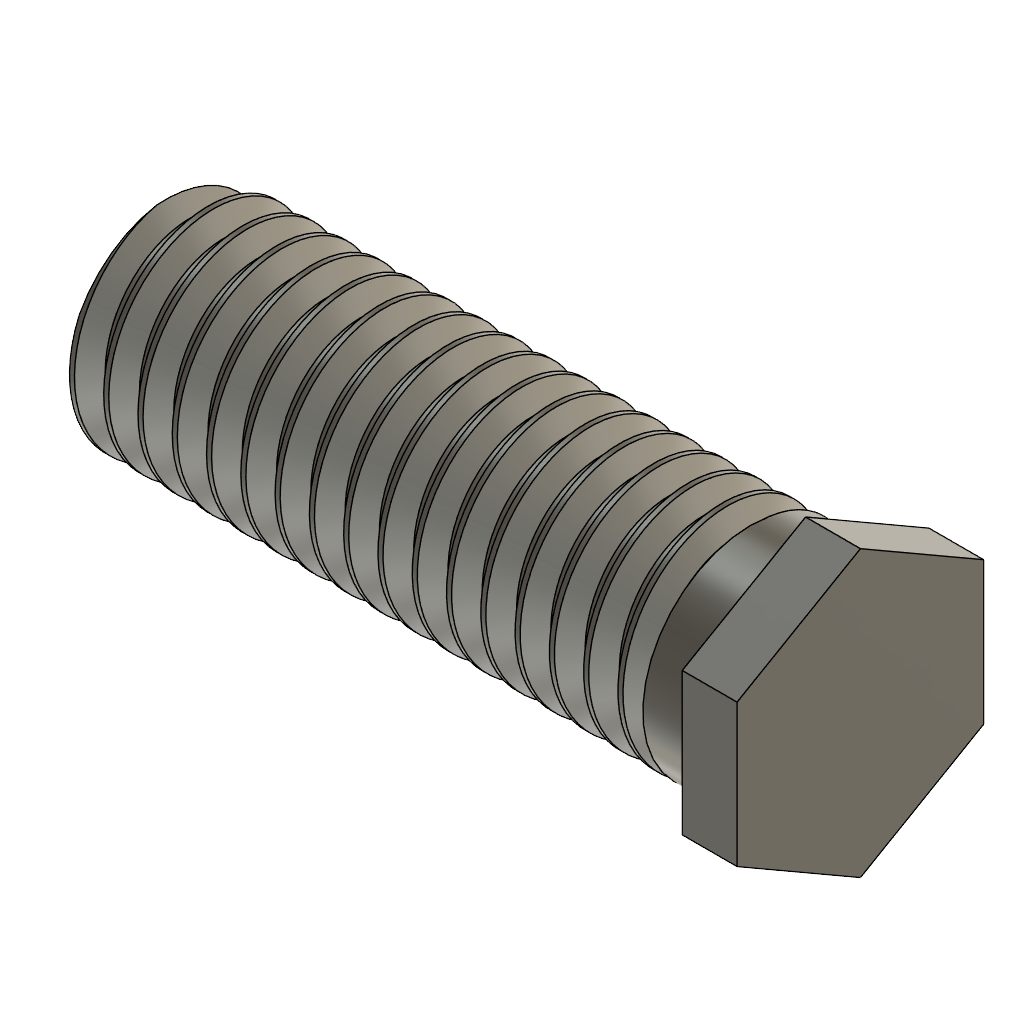
showerhead (Assembly) (Autodesk Fusion 360 archive; units mm, degrees)
design "screw_1_nozzle"
part number: 2026-10-19-10-13-48-495
Autodesk Fusion 360 part; units mm, degrees
sketch "Sketch1" plane through (0, 0, 0) normal (1, 0, 0) x (0, 1, 0)
  circle A0 centre (0, 0) radius 4
  line L0 (-4.4985, 2.5972) -> (-4.4985, -2.5972)
  line L1 (-4.4985, -2.5972) -> (0, -5.1944)
  line L2 (0, -5.1944) -> (4.4985, -2.5972)
  line L3 (4.4985, -2.5972) -> (4.4985, 2.5972)
  line L4 (4.4985, 2.5972) -> (0, 5.1944)
  line L5 (0, 5.1944) -> (-4.4985, 2.5972)
  constraint coincident A0.centre origin
extrude "Extrude1" add sketch "Sketch1" against normal blind 25 contours A0
extrude "Extrude2" add sketch "Sketch1" against normal blind 2
thread "Thread1" "ISO Metric profile 8.0 M8x1.25 M8x1.25 6g" major diameter 7.866 minor diameter 6.4455 pitch 1.25 angle 60 modelled right hand crest width 0.1833 on face at (-9.6667, 3.9801, -0.3983) from (-4, 0, 0) to (-25, 0, 0) crest through (-1.6875, 3.933, 0)

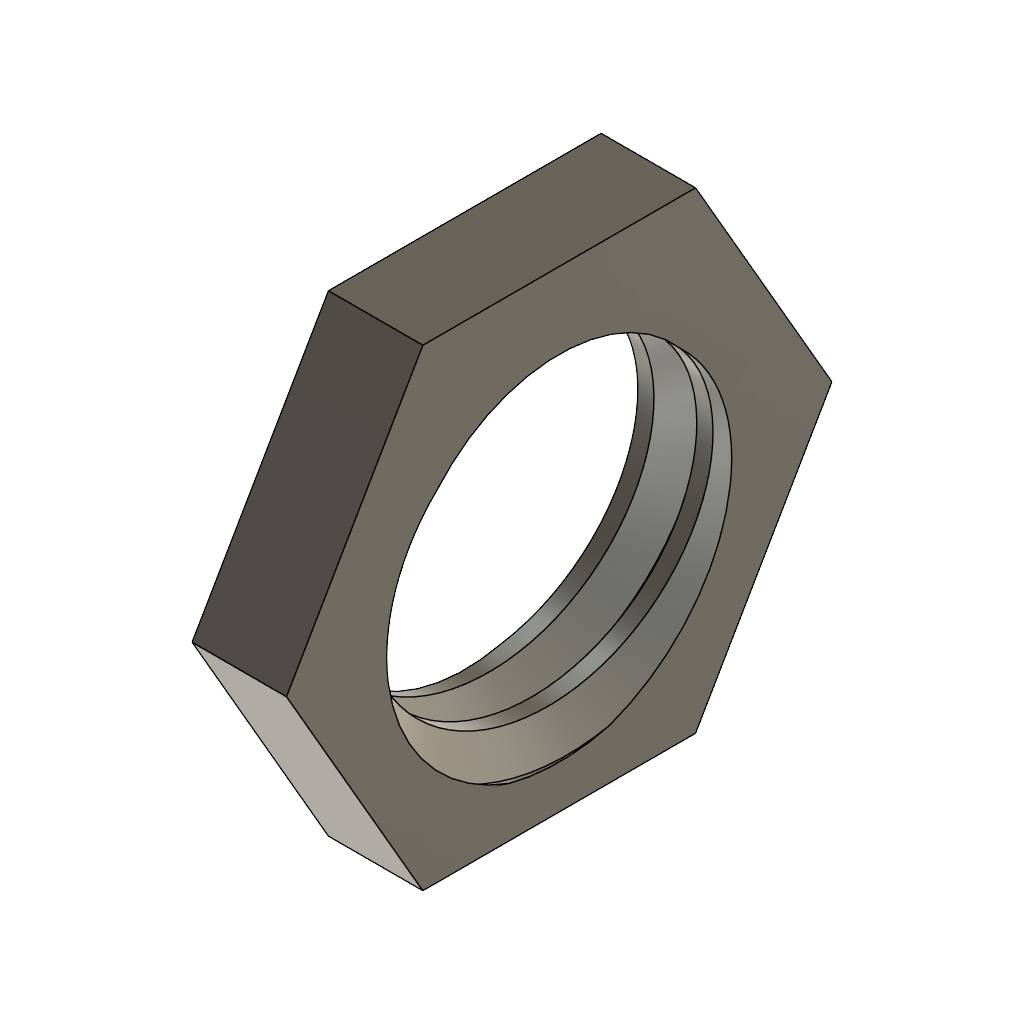
design "nut_1_nozzle"
part number: 2026-10-19-10-17-36-750
Autodesk Fusion 360 part; units mm, degrees
sketch "Sketch1" plane through (0, 0, 0) normal (1, 0, 0) x (0, 1, 0)
  circle A0 centre (0, 0) radius 4
  line L0 (-2.8868, 5) -> (-5.7735, 0)
  line L1 (-5.7735, 0) -> (-2.8868, -5)
  line L2 (-2.8868, -5) -> (2.8868, -5)
  line L3 (2.8868, -5) -> (5.7735, 0)
  line L4 (5.7735, 0) -> (2.8868, 5)
  line L5 (2.8868, 5) -> (-2.8868, 5)
  constraint coincident A0.centre origin
extrude "Extrude1" add sketch "Sketch1" against normal blind 2
thread "Thread1" "ISO Metric profile 8.0 M8x1.25 M8x1.25 6H" major diameter 8.17 minor diameter 6.7795 pitch 1.25 angle 60 modelled right hand crest width 0.343 on face at (-1.3333, 3.995, -0.1994) crest through (-0.3125, 3.3898, 0)

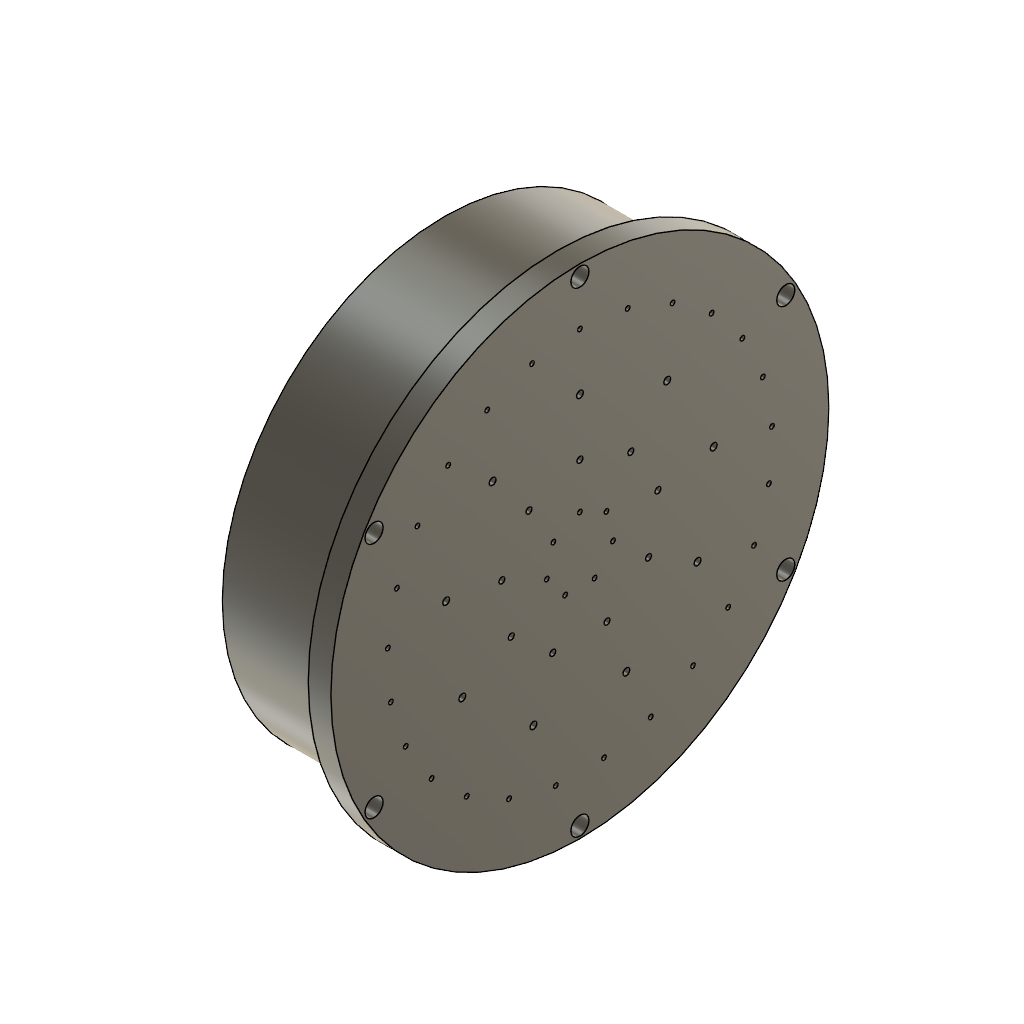
design "showerhead"
part number: 2026-10-19-09-36-01-385
Autodesk Fusion 360 part; units mm, degrees
sketch "Sketch1" plane through (0, 0, 0) normal (1, 0, 0) x (0, 1, 0)
  circle A0 centre (0, 0) radius 110
  circle A1 centre (0, 0) radius 90
  dimension "d1" = 220
  constraint coincident A0.centre A1.centre
  constraint concentric A0 A1
  measures "d1" diameter of A0
extrude "Extrude2" add sketch "Sketch1" along normal blind 10 contours A1
sketch "Sketch3" plane through (10, 0, 0) normal (1, 0, 0) x (0, 1, 0)
  circle A0 centre (0, 0) radius 90
  circle A1 centre (0, 85) radius 1
extrude "Extrude4" cut sketch "Sketch3" against normal blind 31 contours A1
pattern_circular "C-Pattern1" count 25 over 360 about axis through (1.75, 0, 0) along (1, 0, 0) of "Extrude4"
sketch "Sketch4" plane through (10, 0, 0) normal (1, 0, 0) x (0, 1, 0)
  circle A0 centre (0, 0) radius 90
  circle A1 centre (0, 85) radius 1
  circle A2 centre (-21.1386, 82.3296) radius 1
  circle A3 centre (-40.9491, 74.4861) radius 1
  circle A4 centre (-58.1865, 61.9623) radius 1
  circle A5 centre (-71.7679, 45.5453) radius 1
  circle A6 centre (-80.8398, 26.2664) radius 1
  circle A7 centre (-84.8323, 5.3372) radius 1
  circle A8 centre (-83.4944, -15.9274) radius 1
  circle A9 centre (-76.9103, -36.1912) radius 1
  circle A10 centre (-65.4936, -54.181) radius 1
  circle A11 centre (-49.9617, -68.7664) radius 1
  circle A12 centre (-31.2906, -79.031) radius 1
  circle A13 centre (-10.6533, -84.3298) radius 1
  circle A14 centre (10.6533, -84.3298) radius 1
  circle A15 centre (31.2906, -79.031) radius 1
  circle A16 centre (49.9617, -68.7664) radius 1
  circle A17 centre (65.4936, -54.181) radius 1
  circle A18 centre (76.9103, -36.1912) radius 1
  circle A19 centre (83.4944, -15.9274) radius 1
  circle A20 centre (84.8323, 5.3372) radius 1
  circle A21 centre (80.8398, 26.2664) radius 1
  circle A22 centre (71.7679, 45.5453) radius 1
  circle A23 centre (58.1865, 61.9623) radius 1
  circle A24 centre (40.9491, 74.4861) radius 1
  circle A25 centre (21.1386, 82.3296) radius 1
  circle A26 centre (0, 60) radius 1.5
extrude "Extrude5" cut sketch "Sketch4" against normal blind 20 contours A26
pattern_circular "C-Pattern2" count 9 over 360 about axis through (1.75, 0, 0) along (1, 0, 0) of "Extrude5"
sketch "Sketch5" plane through (10, 0, 0) normal (1, 0, 0) x (0, 1, 0)
  circle A0 centre (0, 60) radius 1.5
  circle A1 centre (0, 0) radius 90
  circle A2 centre (0, 85) radius 1
  circle A3 centre (-21.1386, 82.3296) radius 1
  circle A4 centre (-40.9491, 74.4861) radius 1
  circle A5 centre (-58.1865, 61.9623) radius 1
  circle A6 centre (-71.7679, 45.5453) radius 1
  circle A7 centre (-80.8398, 26.2664) radius 1
  circle A8 centre (-84.8323, 5.3372) radius 1
  circle A9 centre (-83.4944, -15.9274) radius 1
  circle A10 centre (-76.9103, -36.1912) radius 1
  circle A11 centre (-65.4936, -54.181) radius 1
  circle A12 centre (-49.9617, -68.7664) radius 1
  circle A13 centre (-31.2906, -79.031) radius 1
  circle A14 centre (-10.6533, -84.3298) radius 1
  circle A15 centre (10.6533, -84.3298) radius 1
  circle A16 centre (31.2906, -79.031) radius 1
  circle A17 centre (49.9617, -68.7664) radius 1
  circle A18 centre (65.4936, -54.181) radius 1
  circle A19 centre (76.9103, -36.1912) radius 1
  circle A20 centre (83.4944, -15.9274) radius 1
  circle A21 centre (84.8323, 5.3372) radius 1
  circle A22 centre (80.8398, 26.2664) radius 1
  circle A23 centre (71.7679, 45.5453) radius 1
  circle A24 centre (58.1865, 61.9623) radius 1
  circle A25 centre (40.9491, 74.4861) radius 1
  circle A26 centre (21.1386, 82.3296) radius 1
  circle A27 centre (-38.5673, 45.9627) radius 1.5
  circle A28 centre (-59.0885, 10.4189) radius 1.5
  circle A29 centre (-51.9615, -30) radius 1.5
  circle A30 centre (-20.5212, -56.3816) radius 1.5
  circle A31 centre (20.5212, -56.3816) radius 1.5
  circle A32 centre (51.9615, -30) radius 1.5
  circle A33 centre (59.0885, 10.4189) radius 1.5
  circle A34 centre (38.5673, 45.9627) radius 1.5
  circle A35 centre (0, 35) radius 1.3026
extrude "Extrude6" cut sketch "Sketch5" against normal blind 25 contours A35
pattern_circular "C-Pattern3" count 9 over 360 about axis through (1.75, 0, 0) along (1, 0, 0) of "Extrude6"
sketch "Sketch6" plane through (10, 0, 0) normal (1, 0, 0) x (0, 1, 0)
  circle A0 centre (0, 35) radius 1.3026
  circle A1 centre (0, 60) radius 1.5
  circle A2 centre (0, 0) radius 90
  circle A3 centre (0, 85) radius 1
  circle A4 centre (-21.1386, 82.3296) radius 1
  circle A5 centre (-40.9491, 74.4861) radius 1
  circle A6 centre (-58.1865, 61.9623) radius 1
  circle A7 centre (-71.7679, 45.5453) radius 1
  circle A8 centre (-80.8398, 26.2664) radius 1
  circle A9 centre (-84.8323, 5.3372) radius 1
  circle A10 centre (-83.4944, -15.9274) radius 1
  circle A11 centre (-76.9103, -36.1912) radius 1
  circle A12 centre (-65.4936, -54.181) radius 1
  circle A13 centre (-49.9617, -68.7664) radius 1
  circle A14 centre (-31.2906, -79.031) radius 1
  circle A15 centre (-10.6533, -84.3298) radius 1
  circle A16 centre (10.6533, -84.3298) radius 1
  circle A17 centre (31.2906, -79.031) radius 1
  circle A18 centre (49.9617, -68.7664) radius 1
  circle A19 centre (65.4936, -54.181) radius 1
  circle A20 centre (76.9103, -36.1912) radius 1
  circle A21 centre (83.4944, -15.9274) radius 1
  circle A22 centre (84.8323, 5.3372) radius 1
  circle A23 centre (80.8398, 26.2664) radius 1
  circle A24 centre (71.7679, 45.5453) radius 1
  circle A25 centre (58.1865, 61.9623) radius 1
  circle A26 centre (40.9491, 74.4861) radius 1
  circle A27 centre (21.1386, 82.3296) radius 1
  circle A28 centre (-38.5673, 45.9627) radius 1.5
  circle A29 centre (-59.0885, 10.4189) radius 1.5
  circle A30 centre (-51.9615, -30) radius 1.5
  circle A31 centre (-20.5212, -56.3816) radius 1.5
  circle A32 centre (20.5212, -56.3816) radius 1.5
  circle A33 centre (51.9615, -30) radius 1.5
  circle A34 centre (59.0885, 10.4189) radius 1.5
  circle A35 centre (38.5673, 45.9627) radius 1.5
  circle A36 centre (-22.4976, 26.8116) radius 1.3026
  circle A37 centre (-34.4683, 6.0777) radius 1.3026
  circle A38 centre (-30.3109, -17.5) radius 1.3026
  circle A39 centre (-11.9707, -32.8892) radius 1.3026
  circle A40 centre (11.9707, -32.8892) radius 1.3026
  circle A41 centre (30.3109, -17.5) radius 1.3026
  circle A42 centre (34.4683, 6.0777) radius 1.3026
  circle A43 centre (22.4976, 26.8116) radius 1.3026
  circle A44 centre (0, 15) radius 1
extrude "Extrude7" cut sketch "Sketch6" against normal blind 25 contours A44
pattern_circular "C-Pattern4" count 7 over 360 about axis through (1.75, 0, 0) along (1, 0, 0) of "Extrude7"
sketch "Sketch7" plane through (0, 0, 0) normal (1, 0, 0) x (0, 1, 0)
  circle A0 centre (0, 105) radius 4
  line L0 (0, 110) -> (0, 109)
  circle A1 centre (-90.9327, 52.5) radius 4
  circle A2 centre (-90.9327, -52.5) radius 4
  circle A3 centre (0, -105) radius 4
  circle A4 centre (90.9327, -52.5) radius 4
  circle A5 centre (90.9327, 52.5) radius 4
  dimension "d28" = 360
  constraint vertical L0
extrude "Extrude8" add sketch "Sketch1" along normal blind 10
extrude "Extrude9" cut sketch "Sketch7" along normal blind 20
sketch "Sketch8" plane through (0, 0, 0) normal (-1, 0, 0) x (0, -1, 0)
  circle A0 centre (-11.7275, 9.3523) radius 1
  circle A1 centre (-14.6239, -3.3378) radius 1
  circle A2 centre (-6.5083, -13.5145) radius 1
  circle A3 centre (6.5083, -13.5145) radius 1
  circle A4 centre (14.6239, -3.3378) radius 1
  circle A5 centre (11.7275, 9.3523) radius 1
  circle A6 centre (-22.4976, 26.8116) radius 1.3026
  circle A7 centre (-34.4683, 6.0777) radius 1.3026
  circle A8 centre (-30.3109, -17.5) radius 1.3026
  circle A9 centre (-11.9707, -32.8892) radius 1.3026
  circle A10 centre (11.9707, -32.8892) radius 1.3026
  circle A11 centre (30.3109, -17.5) radius 1.3026
  circle A12 centre (34.4683, 6.0777) radius 1.3026
  circle A13 centre (22.4976, 26.8116) radius 1.3026
  circle A14 centre (-38.5673, 45.9627) radius 1.5
  circle A15 centre (-59.0885, 10.4189) radius 1.5
  circle A16 centre (-51.9615, -30) radius 1.5
  circle A17 centre (-20.5212, -56.3816) radius 1.5
  circle A18 centre (20.5212, -56.3816) radius 1.5
  circle A19 centre (51.9615, -30) radius 1.5
  circle A20 centre (59.0885, 10.4189) radius 1.5
  circle A21 centre (38.5673, 45.9627) radius 1.5
  circle A22 centre (-21.1386, 82.3296) radius 1
  circle A23 centre (-40.9491, 74.4861) radius 1
  circle A24 centre (-58.1865, 61.9623) radius 1
  circle A25 centre (-71.7679, 45.5453) radius 1
  circle A26 centre (-80.8398, 26.2664) radius 1
  circle A27 centre (-84.8323, 5.3372) radius 1
  circle A28 centre (-83.4944, -15.9274) radius 1
  circle A29 centre (-76.9103, -36.1912) radius 1
  circle A30 centre (-65.4936, -54.181) radius 1
  circle A31 centre (-49.9617, -68.7664) radius 1
  circle A32 centre (-31.2906, -79.031) radius 1
  circle A33 centre (-10.6533, -84.3298) radius 1
  circle A34 centre (10.6533, -84.3298) radius 1
  circle A35 centre (31.2906, -79.031) radius 1
  circle A36 centre (49.9617, -68.7664) radius 1
  circle A37 centre (65.4936, -54.181) radius 1
  circle A38 centre (76.9103, -36.1912) radius 1
  circle A39 centre (83.4944, -15.9274) radius 1
  circle A40 centre (84.8323, 5.3372) radius 1
  circle A41 centre (80.8398, 26.2664) radius 1
  circle A42 centre (71.7679, 45.5453) radius 1
  circle A43 centre (58.1865, 61.9623) radius 1
  circle A44 centre (40.9491, 74.4861) radius 1
  circle A45 centre (21.1386, 82.3296) radius 1
  circle A46 centre (0, 85) radius 1
  circle A47 centre (0, 60) radius 1.5
  circle A48 centre (0, 35) radius 1.3026
  circle A49 centre (0, 15) radius 1
  circle A50 centre (0, 0) radius 110
  circle A51 centre (0, 105) radius 4
  circle A52 centre (90.9327, -52.5) radius 4
  circle A53 centre (0, -105) radius 4
  circle A54 centre (-90.9327, 52.5) radius 4
  circle A55 centre (90.9327, 52.5) radius 4
  circle A56 centre (-90.9327, -52.5) radius 4
  circle A57 centre (0, 0) radius 95
  circle A58 centre (0, 0) radius 98
  constraint concentric A50 A57
  constraint concentric A50 A58
extrude "Extrude10" add sketch "Sketch8" along normal blind 50 contours A58
